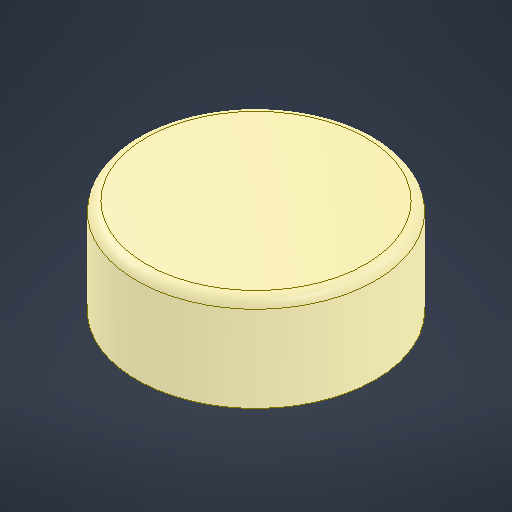
# Autodesk Inventor part: Product Lid
Saved by Autodesk Inventor 2027.1 (Build 311270010, 270A)
## iProperties
Created: 2026-10-02
Part Number: Product Lid
Material: Nylon 6/6
Document SubType Name: Modeling
Designer: Ahmed
Density: 1.13 g/cm^3
Appearance: Nylon 6
Author: Ahmed
Autodesk Inventor part; units mm, degrees
ref_plane "YZ Plane" through (0, 0, 0) normal (1, 0, 0) x (0, 1, 0)
ref_plane "XZ Plane" through (0, 0, 0) normal (0, 1, 0) x (-1, 0, 0)
ref_plane "XY Plane" through (0, 0, 0) normal (0, 0, 1) x (1, 0, 0)
sketch "Sketch3" plane through (0, 0, 0) normal (0, 0, 1) x (1, 0, 0)
  line L0 (0, 0) -> (0, 20)
  line L1 (0, 20) -> (25, 20)
  line L2 (25, 20) -> (25, 0)
  line L3 (0, -4.2992) -> (0, 24.0499) projected
  line L4 (0, 15.5) -> (13.7816, 15.5)
  line L5 (25, 0) -> (24.2184, 0)
  line L6 (22.4412, 1.0827) -> (15.5588, 14.4173)
  arc A0 (15.5588, 14.4173) -> (13.7816, 15.5) centre (13.7816, 13.5) ccw
  arc A1 (22.4412, 1.0827) -> (24.2184, 0) centre (24.2184, 2) ccw
  point P0 (15, 15.5)
  point P1 (23, 0)
  dimension "d6" = 20
  dimension "d7" = 25
  dimension "d14" = 15
  dimension "d15" = 4.5
  dimension "d16" = 2
  dimension "d18" = 2
  dimension "d19" = 17.4428
  constraints: 12 end point, 5 point on line, 4 point on circle, 4 tangent, 3 perpendicular, 2 centre point, 1 equal radius, 1 horizontal, 1 vertical
  measures "d6" distance of L0.start L0.end
  measures "d7" distance of L0.end L1.end
  measures "d14" distance of L4.start point (15, 15.5)
  measures "d15" distance between parallel lines of L4 L1
  measures "d16" distance of L2.end point (23, 0)
  measures "d18" radius of A0
  measures "d19" distance of point (23, 0) point (15, 15.5)
revolve "Revolution1" add sketch "Sketch3" angle 360 about axis through (0, -10, 0) along (0, 1, 0)
fillet "Fillet1" radius 2 1 edges at (-25, 20, 0)
body "Solid3"
